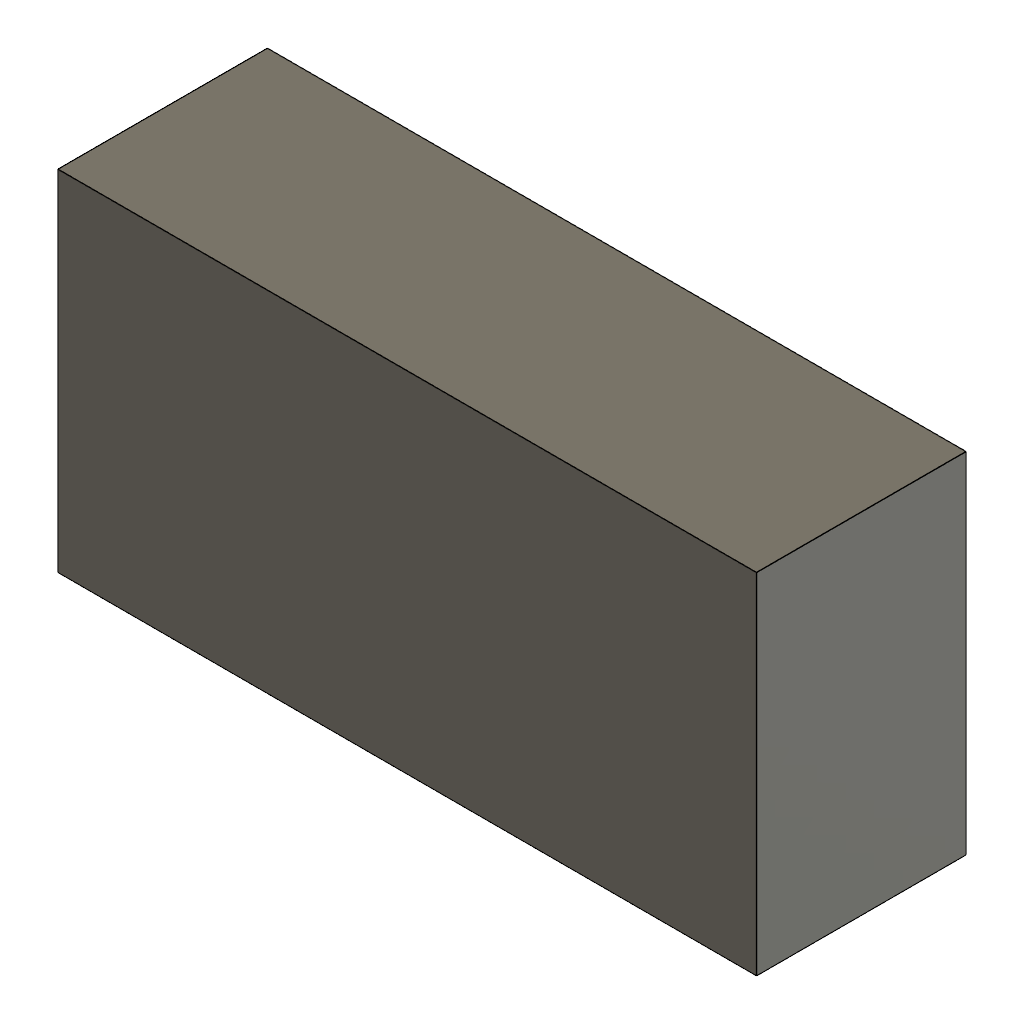
scale_body_about_corner (Autodesk Fusion 360 design; units mm, degrees)
part number: 2026-11-13-14-47-59-672
Autodesk Fusion 360 part; units mm, degrees
sketch "Sketch1" plane through (0, 0, 0) normal (0, 0, 1) x (1, 0, 0)
  line L0 (10, 10) -> (30, 10)
  line L1 (30, 10) -> (30, 20)
  line L2 (30, 20) -> (10, 20)
  line L3 (10, 20) -> (10, 10)
extrude "Extrude1" add sketch "Sketch1" along normal blind 6
scale "Scale1" factor 0.6 about (0, 0, 0) bodies 1
